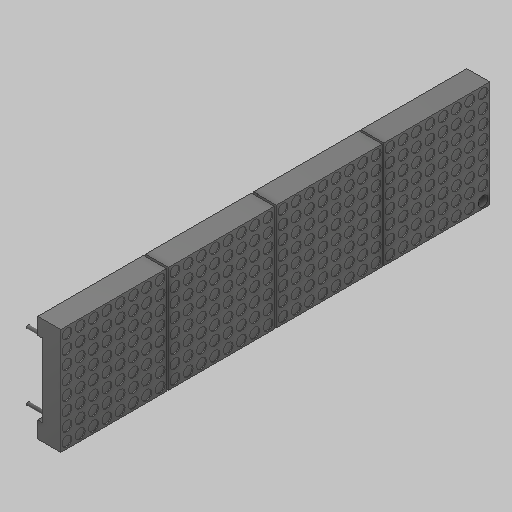
# Autodesk Inventor part: LED_MATRIZ
Saved by Autodesk Inventor 2027 (Build 310192000, 192)
## iProperties
Created: 2026-11-23
Part Number: LED_MATRIZ
Material: Genérico
Document SubType Name: Modeling
Designer: Alexander
Density: 1 g/cm^3
Appearance: Valor por defecto
Author: Alexander
Autodesk Inventor part; units mm, degrees
ref_plane "YZ Plane" through (0, 0, 0) normal (1, 0, 0) x (0, 1, 0)
ref_plane "XZ Plane" through (0, 0, 0) normal (0, 1, 0) x (-1, 0, 0)
ref_plane "XY Plane" through (0, 0, 0) normal (0, 0, 1) x (1, 0, 0)
sketch "Boceto1" plane through (0, 0, 0) normal (1, 0, 0) x (0, 1, 0)
  line L0 (-10.9975, -57.5434) -> (20.9523, -57.5434)
  line L1 (20.9523, -57.5434) -> (20.9523, 71.3287)
  line L2 (20.9523, 71.3287) -> (-10.9975, 71.3287)
  line L3 (-10.9975, 71.3287) -> (-10.9975, -57.5434)
  line L4 (-10.9975, 71.3287) -> (20.9523, 71.3287)
  line L5 (20.9523, 71.3287) -> (20.9523, 39.6092)
  line L6 (20.9523, 39.6092) -> (-10.9975, 39.6092)
  line L7 (-10.9975, 39.6092) -> (-10.9975, 71.3287)
  line L8 (20.9523, 38.9827) -> (-11.1286, 38.9827)
  line L9 (-11.1286, 38.9827) -> (-11.1286, 7.1907)
  line L10 (-11.1286, 7.1907) -> (20.9523, 7.1907)
  line L11 (20.9523, 7.1907) -> (20.9523, 38.9827)
  line L12 (20.9523, 6.6046) -> (-10.9975, 6.6046)
  line L13 (-10.9975, 6.6046) -> (-10.9975, -25.1972)
  line L14 (-10.9975, -25.1972) -> (20.9523, -25.1972)
  line L15 (20.9523, -25.1972) -> (20.9523, 6.6046)
  line L16 (-10.9975, -25.7288) -> (20.9523, -25.7288)
  line L17 (20.9523, -25.7288) -> (20.9523, -57.5434)
  line L18 (20.9523, -57.5434) -> (-10.9975, -57.5434)
  line L19 (-10.9975, -57.5434) -> (-10.9975, -25.7288)
  circle A0 centre (-9.0201, -55.5176) radius 1.5
  point P0 (0, 0)
  point P1 (-10.9975, 6.6046)
  point P2 (-10.9975, 7.1907)
  point P3 (-10.9975, 38.9827)
  point P4 (-10.9975, 39.6092)
  dimension "d0" = 3
  constraints: 40 end point, 10 parallel, 5 horizontal, 5 perpendicular, 5 point on line, 1 centre point
  measures "d0" diameter of A0
extrude "Extrusión1" add sketch "Boceto1" along normal blind 5.6 contours L3 L16 L1 L0 | L3 L12 L1 L14 | L3 L8 L1 L10 | L3 L2 L1 L6
sketch "Boceto2" plane through (0, 0, 0) normal (-1, 0, 0) x (0, 0, 1)
  line L0 (-57.5434, -10.9975) -> (-57.5434, 20.9523) projected
  line L1 (-25.7288, 20.9523) -> (-25.7288, -10.9975) projected
  line L2 (-57.5434, 20.9523) -> (-25.7288, 20.9523)
  line L3 (-25.7288, 20.9523) -> (-25.7288, 15.9523)
  line L4 (-25.7288, 15.9523) -> (-57.5434, 15.9523)
  line L5 (-57.5434, 15.9523) -> (-57.5434, 20.9523)
  line L6 (-57.5434, -10.9975) -> (-25.7288, -10.9975)
  line L7 (-25.7288, -10.9975) -> (-25.7288, -5.9975)
  line L8 (-25.7288, -5.9975) -> (-57.5434, -5.9975)
  line L9 (-57.5434, -5.9975) -> (-57.5434, -10.9975)
  line L10 (-25.1972, -10.9975) -> (-25.1972, 20.9523) projected
  line L11 (6.4707, 20.9523) -> (-25.1972, 20.9523)
  line L12 (-25.1972, 20.9523) -> (-25.1972, 15.9523)
  line L13 (-25.1972, 15.9523) -> (6.4707, 15.9523)
  line L14 (6.4707, 15.9523) -> (6.4707, 20.9523)
  line L15 (6.4707, -10.9975) -> (-25.1972, -10.9975)
  line L16 (-25.1972, -10.9975) -> (-25.1972, -5.9975)
  line L17 (-25.1972, -5.9975) -> (6.4707, -5.9975)
  line L18 (6.4707, -5.9975) -> (6.4707, -10.9975)
  line L19 (38.9827, 20.9523) -> (38.9827, -10.9975) projected
  line L20 (7.1907, -10.9975) -> (7.1907, 20.9523) projected
  line L21 (38.9827, 20.9523) -> (7.1907, 20.9523)
  line L22 (7.1907, 20.9523) -> (7.1907, 15.9523)
  line L23 (7.1907, 15.9523) -> (38.9827, 15.9523)
  line L24 (38.9827, 15.9523) -> (38.9827, 20.9523)
  line L25 (38.9827, -10.9975) -> (7.1907, -10.9975)
  line L26 (7.1907, -10.9975) -> (7.1907, -5.9975)
  line L27 (7.1907, -5.9975) -> (38.9827, -5.9975)
  line L28 (38.9827, -5.9975) -> (38.9827, -10.9975)
  line L29 (71.3287, 20.9523) -> (71.3287, -10.9975) projected
  line L30 (39.6092, -10.9975) -> (39.6092, 20.9523) projected
  line L31 (71.3287, -10.9975) -> (39.6092, -10.9975)
  line L32 (39.6092, -10.9975) -> (39.6092, -5.9975)
  line L33 (39.6092, -5.9975) -> (71.3287, -5.9975)
  line L34 (71.3287, -5.9975) -> (71.3287, -10.9975)
  line L35 (39.6092, 20.9523) -> (71.3287, 20.9523)
  line L36 (71.3287, 20.9523) -> (71.3287, 15.9523)
  line L37 (71.3287, 15.9523) -> (39.6092, 15.9523)
  line L38 (39.6092, 15.9523) -> (39.6092, 20.9523)
  point P0 (0, 0)
  dimension "d3" = 5
  dimension "d4" = 5
  constraints: 64 end point, 20 point on line, 16 parallel, 8 horizontal, 8 perpendicular
  measures "d3" distance of L2.end L3.end
  measures "d4" distance of L7.end L6.end
extrude "Extrusión2" add sketch "Boceto2" along normal blind 1.3 contours L0 L8 L1 L6 | L0 L2 L1 L4 | L10 L11 L14 L13 | L10 L17 L18 L15 | L19 L23 L20 L21 | L19 L25 L20 L27 | L29 L37 L30 L35 | L29 L31 L30 L33
sketch "Boceto3" plane through (5.6, 0, 0) normal (1, 0, 0) x (0, 0, -1)
  circle A0 centre (55.5176, -9.0201) radius 1.5 projected
  circle A1 centre (55.5176, -9.0201) radius 1.5
  line L0 (25.7288, -10.9975) -> (57.5434, -10.9975) projected
  line L1 (57.5434, -10.9975) -> (57.5434, -7.5201)
  line L2 (57.5434, -10.9975) -> (57.5434, 20.9523) projected
  line L3 (57.5434, -10.9975) -> (54.0176, -10.9975)
  circle A2 centre (55.5176, -5.0201) radius 1.5
  circle A3 centre (55.5176, -1.0201) radius 1.5
  circle A4 centre (55.5176, 2.9799) radius 1.5
  circle A5 centre (55.5176, 6.9799) radius 1.5
  circle A6 centre (55.5176, 10.9799) radius 1.5
  circle A7 centre (55.5176, 14.9799) radius 1.5
  circle A8 centre (55.5176, 18.9799) radius 1.5
  circle A9 centre (51.5176, -9.0201) radius 1.5
  circle A10 centre (51.5176, -5.0201) radius 1.5
  circle A11 centre (51.5176, -1.0201) radius 1.5
  circle A12 centre (51.5176, 2.9799) radius 1.5
  circle A13 centre (51.5176, 6.9799) radius 1.5
  circle A14 centre (51.5176, 10.9799) radius 1.5
  circle A15 centre (51.5176, 14.9799) radius 1.5
  circle A16 centre (51.5176, 18.9799) radius 1.5
  circle A17 centre (47.5176, -9.0201) radius 1.5
  circle A18 centre (47.5176, -5.0201) radius 1.5
  circle A19 centre (47.5176, -1.0201) radius 1.5
  circle A20 centre (47.5176, 2.9799) radius 1.5
  circle A21 centre (47.5176, 6.9799) radius 1.5
  circle A22 centre (47.5176, 10.9799) radius 1.5
  circle A23 centre (47.5176, 14.9799) radius 1.5
  circle A24 centre (47.5176, 18.9799) radius 1.5
  circle A25 centre (43.5176, -9.0201) radius 1.5
  circle A26 centre (43.5176, -5.0201) radius 1.5
  circle A27 centre (43.5176, -1.0201) radius 1.5
  circle A28 centre (43.5176, 2.9799) radius 1.5
  circle A29 centre (43.5176, 6.9799) radius 1.5
  circle A30 centre (43.5176, 10.9799) radius 1.5
  circle A31 centre (43.5176, 14.9799) radius 1.5
  circle A32 centre (43.5176, 18.9799) radius 1.5
  circle A33 centre (39.5176, -9.0201) radius 1.5
  circle A34 centre (39.5176, -5.0201) radius 1.5
  circle A35 centre (39.5176, -1.0201) radius 1.5
  circle A36 centre (39.5176, 2.9799) radius 1.5
  circle A37 centre (39.5176, 6.9799) radius 1.5
  circle A38 centre (39.5176, 10.9799) radius 1.5
  circle A39 centre (39.5176, 14.9799) radius 1.5
  circle A40 centre (39.5176, 18.9799) radius 1.5
  circle A41 centre (35.5176, -9.0201) radius 1.5
  circle A42 centre (35.5176, -5.0201) radius 1.5
  circle A43 centre (35.5176, -1.0201) radius 1.5
  circle A44 centre (35.5176, 2.9799) radius 1.5
  circle A45 centre (35.5176, 6.9799) radius 1.5
  circle A46 centre (35.5176, 10.9799) radius 1.5
  circle A47 centre (35.5176, 14.9799) radius 1.5
  circle A48 centre (35.5176, 18.9799) radius 1.5
  circle A49 centre (31.5176, -9.0201) radius 1.5
  circle A50 centre (31.5176, -5.0201) radius 1.5
  circle A51 centre (31.5176, -1.0201) radius 1.5
  circle A52 centre (31.5176, 2.9799) radius 1.5
  circle A53 centre (31.5176, 6.9799) radius 1.5
  circle A54 centre (31.5176, 10.9799) radius 1.5
  circle A55 centre (31.5176, 14.9799) radius 1.5
  circle A56 centre (31.5176, 18.9799) radius 1.5
  circle A57 centre (27.5176, -9.0201) radius 1.5
  circle A58 centre (27.5176, -5.0201) radius 1.5
  circle A59 centre (27.5176, -1.0201) radius 1.5
  circle A60 centre (27.5176, 2.9799) radius 1.5
  circle A61 centre (27.5176, 6.9799) radius 1.5
  circle A62 centre (27.5176, 10.9799) radius 1.5
  circle A63 centre (27.5176, 14.9799) radius 1.5
  circle A64 centre (27.5176, 18.9799) radius 1.5
  circle A65 centre (23.3726, -9.0201) radius 1.5
  circle A66 centre (-9.0761, -9.0201) radius 1.5
  circle A67 centre (-41.5063, -9.0201) radius 1.5
  circle A68 centre (23.3726, -5.0201) radius 1.5
  circle A69 centre (23.3726, -1.0201) radius 1.5
  circle A70 centre (23.3726, 2.9799) radius 1.5
  circle A71 centre (23.3726, 6.9799) radius 1.5
  circle A72 centre (23.3726, 10.9799) radius 1.5
  circle A73 centre (23.3726, 14.9799) radius 1.5
  circle A74 centre (23.3726, 18.9799) radius 1.5
  circle A75 centre (19.3726, -9.0201) radius 1.5
  circle A76 centre (19.3726, -5.0201) radius 1.5
  circle A77 centre (19.3726, -1.0201) radius 1.5
  circle A78 centre (19.3726, 2.9799) radius 1.5
  circle A79 centre (19.3726, 6.9799) radius 1.5
  circle A80 centre (19.3726, 10.9799) radius 1.5
  circle A81 centre (19.3726, 14.9799) radius 1.5
  circle A82 centre (19.3726, 18.9799) radius 1.5
  circle A83 centre (15.3726, -9.0201) radius 1.5
  circle A84 centre (15.3726, -5.0201) radius 1.5
  circle A85 centre (15.3726, -1.0201) radius 1.5
  circle A86 centre (15.3726, 2.9799) radius 1.5
  circle A87 centre (15.3726, 6.9799) radius 1.5
  circle A88 centre (15.3726, 10.9799) radius 1.5
  circle A89 centre (15.3726, 14.9799) radius 1.5
  circle A90 centre (15.3726, 18.9799) radius 1.5
  circle A91 centre (11.3726, -9.0201) radius 1.5
  circle A92 centre (11.3726, -5.0201) radius 1.5
  circle A93 centre (11.3726, -1.0201) radius 1.5
  circle A94 centre (11.3726, 2.9799) radius 1.5
  circle A95 centre (11.3726, 6.9799) radius 1.5
  circle A96 centre (11.3726, 10.9799) radius 1.5
  circle A97 centre (11.3726, 14.9799) radius 1.5
  circle A98 centre (11.3726, 18.9799) radius 1.5
  circle A99 centre (7.3726, -9.0201) radius 1.5
  circle A100 centre (7.3726, -5.0201) radius 1.5
  circle A101 centre (7.3726, -1.0201) radius 1.5
  circle A102 centre (7.3726, 2.9799) radius 1.5
  circle A103 centre (7.3726, 6.9799) radius 1.5
  circle A104 centre (7.3726, 10.9799) radius 1.5
  circle A105 centre (7.3726, 14.9799) radius 1.5
  circle A106 centre (7.3726, 18.9799) radius 1.5
  circle A107 centre (3.3726, -9.0201) radius 1.5
  circle A108 centre (3.3726, -5.0201) radius 1.5
  circle A109 centre (3.3726, -1.0201) radius 1.5
  circle A110 centre (3.3726, 2.9799) radius 1.5
  circle A111 centre (3.3726, 6.9799) radius 1.5
  circle A112 centre (3.3726, 10.9799) radius 1.5
  circle A113 centre (3.3726, 14.9799) radius 1.5
  circle A114 centre (3.3726, 18.9799) radius 1.5
  circle A115 centre (-0.6274, -9.0201) radius 1.5
  circle A116 centre (-0.6274, -5.0201) radius 1.5
  circle A117 centre (-0.6274, -1.0201) radius 1.5
  circle A118 centre (-0.6274, 2.9799) radius 1.5
  circle A119 centre (-0.6274, 6.9799) radius 1.5
  circle A120 centre (-0.6274, 10.9799) radius 1.5
  circle A121 centre (-0.6274, 14.9799) radius 1.5
  circle A122 centre (-0.6274, 18.9799) radius 1.5
  circle A123 centre (-4.6274, -9.0201) radius 1.5
  circle A124 centre (-4.6274, -5.0201) radius 1.5
  circle A125 centre (-4.6274, -1.0201) radius 1.5
  circle A126 centre (-4.6274, 2.9799) radius 1.5
  circle A127 centre (-4.6274, 6.9799) radius 1.5
  circle A128 centre (-4.6274, 10.9799) radius 1.5
  circle A129 centre (-4.6274, 14.9799) radius 1.5
  circle A130 centre (-4.6274, 18.9799) radius 1.5
  circle A131 centre (-13.0761, -9.0201) radius 1.5
  circle A132 centre (-17.0761, -9.0201) radius 1.5
  circle A133 centre (-21.0761, -9.0201) radius 1.5
  circle A134 centre (-25.0761, -9.0201) radius 1.5
  circle A135 centre (-29.0761, -9.0201) radius 1.5
  circle A136 centre (-33.0761, -9.0201) radius 1.5
  circle A137 centre (-37.0761, -9.0201) radius 1.5
  circle A138 centre (-9.0761, -5.0201) radius 1.5
  circle A139 centre (-13.0761, -5.0201) radius 1.5
  circle A140 centre (-17.0761, -5.0201) radius 1.5
  circle A141 centre (-21.0761, -5.0201) radius 1.5
  circle A142 centre (-25.0761, -5.0201) radius 1.5
  circle A143 centre (-29.0761, -5.0201) radius 1.5
  circle A144 centre (-33.0761, -5.0201) radius 1.5
  circle A145 centre (-37.0761, -5.0201) radius 1.5
  circle A146 centre (-9.0761, -1.0201) radius 1.5
  circle A147 centre (-13.0761, -1.0201) radius 1.5
  circle A148 centre (-17.0761, -1.0201) radius 1.5
  circle A149 centre (-21.0761, -1.0201) radius 1.5
  circle A150 centre (-25.0761, -1.0201) radius 1.5
  circle A151 centre (-29.0761, -1.0201) radius 1.5
  circle A152 centre (-33.0761, -1.0201) radius 1.5
  circle A153 centre (-37.0761, -1.0201) radius 1.5
  circle A154 centre (-9.0761, 2.9799) radius 1.5
  circle A155 centre (-13.0761, 2.9799) radius 1.5
  circle A156 centre (-17.0761, 2.9799) radius 1.5
  circle A157 centre (-21.0761, 2.9799) radius 1.5
  circle A158 centre (-25.0761, 2.9799) radius 1.5
  circle A159 centre (-29.0761, 2.9799) radius 1.5
  circle A160 centre (-33.0761, 2.9799) radius 1.5
  circle A161 centre (-37.0761, 2.9799) radius 1.5
  circle A162 centre (-9.0761, 6.9799) radius 1.5
  circle A163 centre (-13.0761, 6.9799) radius 1.5
  circle A164 centre (-17.0761, 6.9799) radius 1.5
  circle A165 centre (-21.0761, 6.9799) radius 1.5
  circle A166 centre (-25.0761, 6.9799) radius 1.5
  circle A167 centre (-29.0761, 6.9799) radius 1.5
  circle A168 centre (-33.0761, 6.9799) radius 1.5
  circle A169 centre (-37.0761, 6.9799) radius 1.5
  circle A170 centre (-9.0761, 10.9799) radius 1.5
  circle A171 centre (-13.0761, 10.9799) radius 1.5
  circle A172 centre (-17.0761, 10.9799) radius 1.5
  circle A173 centre (-21.0761, 10.9799) radius 1.5
  circle A174 centre (-25.0761, 10.9799) radius 1.5
  circle A175 centre (-29.0761, 10.9799) radius 1.5
  circle A176 centre (-33.0761, 10.9799) radius 1.5
  circle A177 centre (-37.0761, 10.9799) radius 1.5
  circle A178 centre (-9.0761, 14.9799) radius 1.5
  circle A179 centre (-13.0761, 14.9799) radius 1.5
  circle A180 centre (-17.0761, 14.9799) radius 1.5
  circle A181 centre (-21.0761, 14.9799) radius 1.5
  circle A182 centre (-25.0761, 14.9799) radius 1.5
  circle A183 centre (-29.0761, 14.9799) radius 1.5
  circle A184 centre (-33.0761, 14.9799) radius 1.5
  circle A185 centre (-37.0761, 14.9799) radius 1.5
  circle A186 centre (-9.0761, 18.9799) radius 1.5
  circle A187 centre (-13.0761, 18.9799) radius 1.5
  circle A188 centre (-17.0761, 18.9799) radius 1.5
  circle A189 centre (-21.0761, 18.9799) radius 1.5
  circle A190 centre (-25.0761, 18.9799) radius 1.5
  circle A191 centre (-29.0761, 18.9799) radius 1.5
  circle A192 centre (-33.0761, 18.9799) radius 1.5
  circle A193 centre (-37.0761, 18.9799) radius 1.5
  circle A194 centre (-41.5063, -5.0201) radius 1.5
  circle A195 centre (-41.5063, -1.0201) radius 1.5
  circle A196 centre (-41.5063, 2.9799) radius 1.5
  circle A197 centre (-41.5063, 6.9799) radius 1.5
  circle A198 centre (-41.5063, 10.9799) radius 1.5
  circle A199 centre (-41.5063, 14.9799) radius 1.5
  circle A200 centre (-41.5063, 18.9799) radius 1.5
  circle A201 centre (-45.5063, -9.0201) radius 1.5
  circle A202 centre (-45.5063, -5.0201) radius 1.5
  circle A203 centre (-45.5063, -1.0201) radius 1.5
  circle A204 centre (-45.5063, 2.9799) radius 1.5
  circle A205 centre (-45.5063, 6.9799) radius 1.5
  circle A206 centre (-45.5063, 10.9799) radius 1.5
  circle A207 centre (-45.5063, 14.9799) radius 1.5
  circle A208 centre (-45.5063, 18.9799) radius 1.5
  circle A209 centre (-49.5063, -9.0201) radius 1.5
  circle A210 centre (-49.5063, -5.0201) radius 1.5
  circle A211 centre (-49.5063, -1.0201) radius 1.5
  circle A212 centre (-49.5063, 2.9799) radius 1.5
  circle A213 centre (-49.5063, 6.9799) radius 1.5
  circle A214 centre (-49.5063, 10.9799) radius 1.5
  circle A215 centre (-49.5063, 14.9799) radius 1.5
  circle A216 centre (-49.5063, 18.9799) radius 1.5
  circle A217 centre (-53.5063, -9.0201) radius 1.5
  circle A218 centre (-53.5063, -5.0201) radius 1.5
  circle A219 centre (-53.5063, -1.0201) radius 1.5
  circle A220 centre (-53.5063, 2.9799) radius 1.5
  circle A221 centre (-53.5063, 6.9799) radius 1.5
  circle A222 centre (-53.5063, 10.9799) radius 1.5
  circle A223 centre (-53.5063, 14.9799) radius 1.5
  circle A224 centre (-53.5063, 18.9799) radius 1.5
  circle A225 centre (-57.5063, -9.0201) radius 1.5
  circle A226 centre (-57.5063, -5.0201) radius 1.5
  circle A227 centre (-57.5063, -1.0201) radius 1.5
  circle A228 centre (-57.5063, 2.9799) radius 1.5
  circle A229 centre (-57.5063, 6.9799) radius 1.5
  circle A230 centre (-57.5063, 10.9799) radius 1.5
  circle A231 centre (-57.5063, 14.9799) radius 1.5
  circle A232 centre (-57.5063, 18.9799) radius 1.5
  circle A233 centre (-61.5063, -9.0201) radius 1.5
  circle A234 centre (-61.5063, -5.0201) radius 1.5
  circle A235 centre (-61.5063, -1.0201) radius 1.5
  circle A236 centre (-61.5063, 2.9799) radius 1.5
  circle A237 centre (-61.5063, 6.9799) radius 1.5
  circle A238 centre (-61.5063, 10.9799) radius 1.5
  circle A239 centre (-61.5063, 14.9799) radius 1.5
  circle A240 centre (-61.5063, 18.9799) radius 1.5
  circle A241 centre (-65.5063, -9.0201) radius 1.5
  circle A242 centre (-65.5063, -5.0201) radius 1.5
  circle A243 centre (-65.5063, -1.0201) radius 1.5
  circle A244 centre (-65.5063, 2.9799) radius 1.5
  circle A245 centre (-65.5063, 6.9799) radius 1.5
  circle A246 centre (-65.5063, 10.9799) radius 1.5
  circle A247 centre (-65.5063, 14.9799) radius 1.5
  circle A248 centre (-65.5063, 18.9799) radius 1.5
  circle A249 centre (-69.5063, -9.0201) radius 1.5
  circle A250 centre (-69.5063, -5.0201) radius 1.5
  circle A251 centre (-69.5063, -1.0201) radius 1.5
  circle A252 centre (-69.5063, 2.9799) radius 1.5
  circle A253 centre (-69.5063, 6.9799) radius 1.5
  circle A254 centre (-69.5063, 10.9799) radius 1.5
  circle A255 centre (-69.5063, 14.9799) radius 1.5
  circle A256 centre (-69.5063, 18.9799) radius 1.5
  point P0 (0, 0)
  dimension "d9" = 4
  dimension "d12" = 4
  dimension "d15" = 3
  dimension "d16" = 3
  dimension "d17" = 3
  dimension "d20" = 4
  dimension "d23" = 4
  dimension "d28" = 4
  dimension "d31" = 4
  dimension "d36" = 4
  dimension "d39" = 4
  constraints: 256 centre point, 5 horizontal, 4 end point, 4 vertical, 1 coincident, 1 point on line, 504 other
  measures "d9" distance of A1.centre A2.centre
  measures "d12" distance of A1.centre A9.centre
  measures "d15" diameter of A65
  measures "d16" diameter of A66
  measures "d17" diameter of A67
  measures "d20" distance of A65.centre A68.centre
  measures "d23" distance of A65.centre A75.centre
  measures "d28" distance of A66.centre A131.centre
  measures "d31" distance of A66.centre A138.centre
  measures "d36" distance of A67.centre A194.centre
  measures "d39" distance of A67.centre A201.centre
extrude "Extrusión3" cut sketch "Boceto3" against normal blind 0.3
sketch "Boceto4" plane through (0, 0, 0) normal (-1, 0, 0) x (0, 0, 1)
  circle A0 centre (-55.5176, 14.9799) radius 1.5 projected
  circle A1 centre (-55.5176, 14.9799) radius 0.5
  circle A2 centre (-55.5176, -5.0201) radius 1.5 projected
  circle A3 centre (-55.5176, -5.0201) radius 0.5
  circle A4 centre (-27.5176, 14.9799) radius 1.5 projected
  circle A5 centre (-27.5176, 14.9799) radius 0.5
  circle A6 centre (-27.5176, -5.0201) radius 1.5 projected
  circle A7 centre (-27.5176, -5.0201) radius 0.5
  circle A8 centre (69.5063, 14.9799) radius 1.5 projected
  circle A9 centre (69.5063, 14.9799) radius 0.5
  circle A10 centre (69.5063, -5.0201) radius 1.5 projected
  circle A11 centre (69.5063, -5.0201) radius 0.5
  circle A12 centre (41.5063, 14.9799) radius 1.5 projected
  circle A13 centre (41.5063, 14.9799) radius 0.5
  circle A14 centre (41.5063, -5.0201) radius 1.5 projected
  circle A15 centre (41.5063, -5.0201) radius 0.5
  point P0 (0, 0)
  dimension "d44" = 1
  dimension "d45" = 1
  dimension "d46" = 1
  dimension "d47" = 1
  dimension "d48" = 1
  dimension "d49" = 1
  dimension "d50" = 1
  dimension "d51" = 1
  constraints: 8 centre point, 8 coincident
  measures "d44" diameter of A1
  measures "d45" diameter of A3
  measures "d46" diameter of A5
  measures "d47" diameter of A7
  measures "d48" diameter of A9
  measures "d49" diameter of A11
  measures "d50" diameter of A13
  measures "d51" diameter of A15
extrude "Extrusión4" add sketch "Boceto4" along normal blind 6 contours A1 | A3 | A5 | A7 | A9 | A11 | A13 | A15
